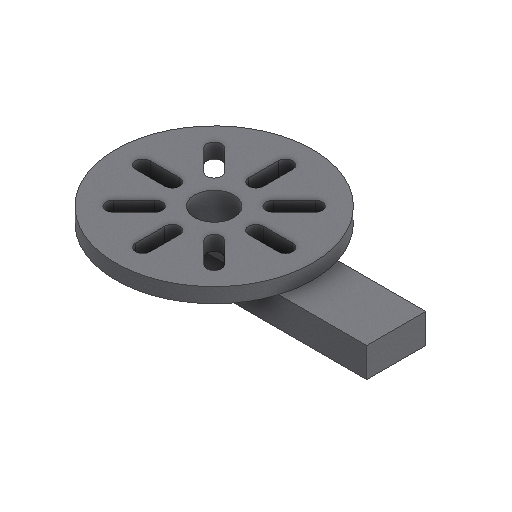
# Autodesk Inventor part: mesa
Saved by Autodesk Inventor 2027.1 (Build 311270010, 270A)
## iProperties
Created: 2026-11-17
Part Number: mesa
Material: Generic
Document SubType Name: Modeling
Designer: migue
Density: 1 g/cm^3
Appearance: Default
Mass: 703.82 g
Surface Area: 1039.4 cm^2
Volume: 703.82 cm^3
Author: migue
Autodesk Inventor part; units mm, degrees
ref_plane "YZ Plane" through (0, 0, 0) normal (1, 0, 0) x (0, 1, 0)
ref_plane "XZ Plane" through (0, 0, 0) normal (0, 1, 0) x (-1, 0, 0)
ref_plane "XY Plane" through (0, 0, 0) normal (0, 0, 1) x (1, 0, 0)
sketch "Sketch1" plane through (0, 0, 0) normal (0, 1, 0) x (-1, 0, 0)
  circle A0 centre (0, 0) radius 100
  circle A1 centre (0, 0) radius 20
  line L0 (0, 0) -> (0, -130.0878) construction
  line L1 (42.5, 7.5) -> (72.5, 7.5)
  line L2 (72.5, 7.5) -> (72.5, -7.5) construction
  line L3 (72.5, -7.5) -> (42.5, -7.5)
  line L4 (42.5, -7.5) -> (42.5, 7.5) construction
  line L5 (42.5, 7.5) -> (72.5, -7.5) construction
  line L6 (72.5, 7.5) -> (42.5, -7.5) construction
  arc A2 (42.5, 7.5) -> (42.5, -7.5) centre (42.5, 0) ccw
  arc A3 (72.5, -7.5) -> (72.5, 7.5) centre (72.5, 0) ccw
  line L7 (0, 0) -> (91.2174, 0) construction
  line L8 (24.7487, 35.3553) -> (45.9619, 56.5685)
  line L9 (45.9619, 56.5685) -> (56.5685, 45.9619) construction
  line L10 (56.5685, 45.9619) -> (35.3553, 24.7487)
  line L11 (35.3553, 24.7487) -> (24.7487, 35.3553) construction
  line L12 (24.7487, 35.3553) -> (56.5685, 45.9619) construction
  line L13 (45.9619, 56.5685) -> (35.3553, 24.7487) construction
  arc A4 (24.7487, 35.3553) -> (35.3553, 24.7487) centre (30.052, 30.052) ccw
  arc A5 (56.5685, 45.9619) -> (45.9619, 56.5685) centre (51.2652, 51.2652) ccw
  line L14 (-7.5, 42.5) -> (-7.5, 72.5)
  line L15 (-7.5, 72.5) -> (7.5, 72.5) construction
  line L16 (7.5, 72.5) -> (7.5, 42.5)
  line L17 (7.5, 42.5) -> (-7.5, 42.5) construction
  line L18 (-7.5, 42.5) -> (7.5, 72.5) construction
  line L19 (-7.5, 72.5) -> (7.5, 42.5) construction
  arc A6 (-7.5, 42.5) -> (7.5, 42.5) centre (0, 42.5) ccw
  arc A7 (7.5, 72.5) -> (-7.5, 72.5) centre (0, 72.5) ccw
  line L20 (-35.3553, 24.7487) -> (-56.5685, 45.9619)
  line L21 (-56.5685, 45.9619) -> (-45.9619, 56.5685) construction
  line L22 (-45.9619, 56.5685) -> (-24.7487, 35.3553)
  line L23 (-24.7487, 35.3553) -> (-35.3553, 24.7487) construction
  line L24 (-35.3553, 24.7487) -> (-45.9619, 56.5685) construction
  line L25 (-56.5685, 45.9619) -> (-24.7487, 35.3553) construction
  arc A8 (-35.3553, 24.7487) -> (-24.7487, 35.3553) centre (-30.052, 30.052) ccw
  arc A9 (-45.9619, 56.5685) -> (-56.5685, 45.9619) centre (-51.2652, 51.2652) ccw
  line L26 (-42.5, -7.5) -> (-72.5, -7.5)
  line L27 (-72.5, -7.5) -> (-72.5, 7.5) construction
  line L28 (-72.5, 7.5) -> (-42.5, 7.5)
  line L29 (-42.5, 7.5) -> (-42.5, -7.5) construction
  line L30 (-42.5, -7.5) -> (-72.5, 7.5) construction
  line L31 (-72.5, -7.5) -> (-42.5, 7.5) construction
  arc A10 (-42.5, -7.5) -> (-42.5, 7.5) centre (-42.5, 0) ccw
  arc A11 (-72.5, 7.5) -> (-72.5, -7.5) centre (-72.5, 0) ccw
  line L32 (-24.7487, -35.3553) -> (-45.9619, -56.5685)
  line L33 (-45.9619, -56.5685) -> (-56.5685, -45.9619) construction
  line L34 (-56.5685, -45.9619) -> (-35.3553, -24.7487)
  line L35 (-35.3553, -24.7487) -> (-24.7487, -35.3553) construction
  line L36 (-24.7487, -35.3553) -> (-56.5685, -45.9619) construction
  line L37 (-45.9619, -56.5685) -> (-35.3553, -24.7487) construction
  arc A12 (-24.7487, -35.3553) -> (-35.3553, -24.7487) centre (-30.052, -30.052) ccw
  arc A13 (-56.5685, -45.9619) -> (-45.9619, -56.5685) centre (-51.2652, -51.2652) ccw
  line L38 (7.5, -42.5) -> (7.5, -72.5)
  line L39 (7.5, -72.5) -> (-7.5, -72.5) construction
  line L40 (-7.5, -72.5) -> (-7.5, -42.5)
  line L41 (-7.5, -42.5) -> (7.5, -42.5) construction
  line L42 (7.5, -42.5) -> (-7.5, -72.5) construction
  line L43 (7.5, -72.5) -> (-7.5, -42.5) construction
  arc A14 (7.5, -42.5) -> (-7.5, -42.5) centre (0, -42.5) ccw
  arc A15 (-7.5, -72.5) -> (7.5, -72.5) centre (0, -72.5) ccw
  line L44 (35.3553, -24.7487) -> (56.5685, -45.9619)
  line L45 (56.5685, -45.9619) -> (45.9619, -56.5685) construction
  line L46 (45.9619, -56.5685) -> (24.7487, -35.3553)
  line L47 (24.7487, -35.3553) -> (35.3553, -24.7487) construction
  line L48 (35.3553, -24.7487) -> (45.9619, -56.5685) construction
  line L49 (56.5685, -45.9619) -> (24.7487, -35.3553) construction
  arc A16 (35.3553, -24.7487) -> (24.7487, -35.3553) centre (30.052, -30.052) ccw
  arc A17 (45.9619, -56.5685) -> (56.5685, -45.9619) centre (51.2652, -51.2652) ccw
  point P0 (57.5, 0)
  point P1 (35, 0)
  point P2 (40.6586, 40.6586)
  point P3 (24.7487, 24.7487)
  point P4 (0, 57.5)
  point P5 (0, 35)
  point P6 (-40.6586, 40.6586)
  point P7 (-24.7487, 24.7487)
  point P8 (-57.5, 0)
  point P9 (-35, 0)
  point P10 (-40.6586, -40.6586)
  point P11 (-24.7487, -24.7487)
  point P12 (0, -57.5)
  point P13 (0, -35)
  point P14 (40.6586, -40.6586)
  point P15 (24.7487, -24.7487)
  dimension "d0" = 200
  dimension "d1" = 40
  dimension "d14" = 30
  dimension "d15" = 15
  dimension "d16" = 35
  dimension "d19" = 360
  constraints: 100 end point, 33 point on circle, 18 centre point, 4 tangent, 3 coincident, 2 horizontal, 2 midpoint, 2 parallel, 1 perpendicular, 1 point on line, 1 vertical, 129 other
  measures "d0" diameter of A0
  measures "d1" diameter of A1
  measures "d14" distance of L2.end L3.end
  measures "d15" distance of L1.end L2.end
  measures "d16" distance of A1.centre point (35, 0)
extrude "Extrusion1" add sketch "Sketch1" along normal blind 15
sketch "Sketch2" plane through (0, 0, 0) normal (0, -1, 0) x (1, 0, 0)
  circle A0 centre (0, 0) radius 30
  circle A1 centre (0, 0) radius 20 projected
  dimension "d11" = 60
  constraints: 1 centre point, 1 coincident
  measures "d11" diameter of A0
extrude "Extrusion2" add sketch "Sketch2" along normal blind 15
sketch "Sketch3" plane through (0, 0, 0) normal (1, 0, 0) x (0, 1, 0)
  line L0 (-15, 30) -> (-15, -30) projected
  line L1 (0, 30) -> (-15, 30) projected
  line L2 (0, -30) -> (-15, -30) projected
  line L3 (-30, 30) -> (0, 30)
  line L4 (0, 30) -> (0, -30)
  line L5 (0, -30) -> (-30, -30)
  line L6 (-30, -30) -> (-30, 30)
  line L7 (-30, 30) -> (0, -30) construction
  line L8 (0, 30) -> (-30, -30) construction
  point P0 (0, 0)
  point P1 (-15, 0)
  constraints: 12 end point, 3 midpoint, 2 parallel, 1 horizontal, 1 perpendicular
extrude "Extrusion3" add sketch "Sketch3" along normal blind 185
sketch "Sketch4" plane through (0, -15, 0) normal (0, -1, 0) x (1, 0, 0)
  arc A0 (0, 20) -> (0, -20) centre (0, 0) ccw projected
  arc A1 (0, 30) -> (0, -30) centre (0, 0) ccw projected
  circle A2 centre (0, 0) radius 20
  circle A3 centre (0, 0) radius 30
  point P0 (0, -20)
  constraints: 2 centre point, 2 coincident, 2 concentric
extrude "Extrusion4" cut sketch "Sketch4" along normal mid plane 185 contours A2 A0
fillet "Fillet1" radius 12.75 2 edges at (0, -15, -25) (0, -15, 25)
body "Solid1"
